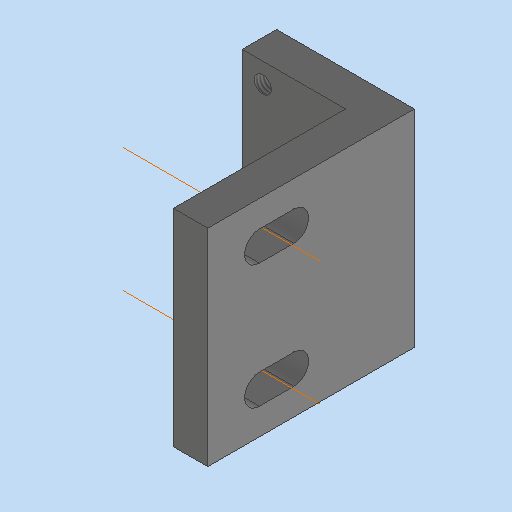
# Autodesk Inventor part: MM0948AN100_G01_210
Saved by Autodesk Inventor 2023.3 (Build 273359000, 359)
## iProperties
Created: 2024-02-27
Part Number: MM0948AN100_G01_210
Material: 1.2099 X5CrS12
Description: =<RBPARTNOTITLE2>
Document SubType Name: Modeling
Designer: RIC7AN
Mass: 49.787 g
Surface Area: 35.9926 cm^2
Volume: 6.34229 cm^3
Density: 7.85 g/cm^3
Appearance: Stahl - rostfrei AnP
RBPARTMADEOF: 30 x 30 x 20 (FM)
RBDRAWINGMISSINGSPEC: --
AnP_Kategorie: 1
RBPARTNOTITLE2: Anfertigungsteil
RBSURFACE: --
RBPARTNOTITLE1: manufactured part
RBSURFACE2: --
AnP_Material: =<Material>
RBMATERIAL: =<Material>
RBMATNO: =<Part Number>
RBPARTNO: SIEHE MNR
MaxAbmaße: 30 x 30 x 20 (FM)
Author: RIC7AN
Keywords: =<RBPARTMADEOF>
Comments: =<RBSURFACE2>
Revision Number: 01
Autodesk Inventor part; units mm, degrees
ref_plane "YZ Plane" through (0, 0, 0) normal (1, 0, 0) x (0, 1, 0)
ref_plane "XZ Plane" through (0, 0, 0) normal (0, 1, 0) x (-1, 0, 0)
ref_plane "XY Plane" through (0, 0, 0) normal (0, 0, 1) x (1, 0, 0)
sketch "Skizze1" plane through (0, 0, 0) normal (0, 0, 1) x (1, 0, 0)
  line L0 (-20, 0) -> (0, 0)
  line L1 (0, 0) -> (0, 5)
  line L2 (0, 5) -> (-20, 5)
  line L3 (-20, 5) -> (-20, 0)
  line L4 (0, 0) -> (-5, 0)
  line L5 (-5, 0) -> (-5, -25)
  line L6 (-5, -25) -> (0, -25)
  line L7 (0, -25) -> (0, 0)
  line L8 (-24, 0) -> (4, 0) projected
  line L9 (0, 11) -> (0, -31) projected
  point P0 (0, 0)
  dimension "d0" = 20
  dimension "d1" = 30
  dimension "d2" = 5
  dimension "d3" = 5
  constraints: 16 end point, 4 parallel, 2 collinear, 2 horizontal, 2 perpendicular
  measures "d0" distance between parallel lines of L7 L3
  measures "d1" distance between parallel lines of L6 L2
  measures "d2" distance of L2.end L0.start
  measures "d3" distance of L5.end L6.end
extrude "Extrusion1" add sketch "Skizze1" along normal mid plane 30
sketch "Skizze2" plane through (-20, 5, 15) normal (0, 1, 0) x (1, 0, 0)
  line L0 (0, 30) -> (0, 0) projected
  line L1 (24, 15) -> (-4, 15) projected
  point P0 (20, 15)
  point P1 (3, 27.075)
  point P2 (3, 2.925)
  dimension "d6" = 24.15
  dimension "d7" = 3
  constraints: 1 symmetric about line
  measures "d6" distance of point (3, 2.925) point (3, 27.075)
  measures "d7" distance from line of point (3, 27.075) L0
hole "Bohrung1" at (-17, 5, -12.075) at (-17, 5, 12.075) direction (0, -1, 0) diameter 2.459 end through all thread size "M3x0.5" designation "M3" class "6H" standard "ISO Metric profile"
sketch "Skizze3" plane through (-5, -25, 15) normal (-1, 0, 0) x (0, 0, 1)
  line L0 (-30, 0) -> (0, 0) projected
  line L1 (0, 25) -> (0, 0) projected
  line L2 (-30, 25) -> (0, 25) projected
  line L3 (-30, 0) -> (-30, 25) projected
  line L4 (-24, 12.5) -> (-24, 7.5) construction
  line L5 (-26.15, 12.5) -> (-26.15, 7.5)
  line L6 (-21.85, 7.5) -> (-21.85, 12.5)
  arc A0 (-21.85, 12.5) -> (-26.15, 12.5) centre (-24, 12.5) ccw
  arc A1 (-26.15, 7.5) -> (-21.85, 7.5) centre (-24, 7.5) ccw
  line L7 (-6, 12.5) -> (-6, 7.5) construction
  line L8 (-8.15, 12.5) -> (-8.15, 7.5)
  line L9 (-3.85, 7.5) -> (-3.85, 12.5)
  arc A2 (-3.85, 12.5) -> (-8.15, 12.5) centre (-6, 12.5) ccw
  arc A3 (-8.15, 7.5) -> (-3.85, 7.5) centre (-6, 7.5) ccw
  line L10 (-15, 36) -> (-15, -6) projected
  point P0 (-15, 25)
  point P1 (-24, 10)
  point P2 (-6, 10)
  dimension "d15" = 4.3
  dimension "d16" = 4.3
  dimension "d17" = 5
  dimension "d18" = 5
  dimension "d19" = 18
  dimension "d20" = 10
  constraints: 16 end point, 8 point on circle, 8 tangent, 4 centre point, 4 parallel, 2 midpoint, 1 horizontal alignment, 1 other
  measures "d15" distance between parallel lines of L6 L5
  measures "d16" distance between parallel lines of L9 L8
  measures "d17" distance of L4.start L4.end
  measures "d18" distance of L7.start L7.end
  measures "d19" distance between parallel lines of L7 L4
  measures "d20" distance from line of L0 point (-24, 10)
extrude "Extrusion2" cut sketch "Skizze3" against normal through all contours A0 L6 A1 L5 | A2 L9 A3 L8
equation "\"d16\" = d15"
equation "\"d18\" = d17"
